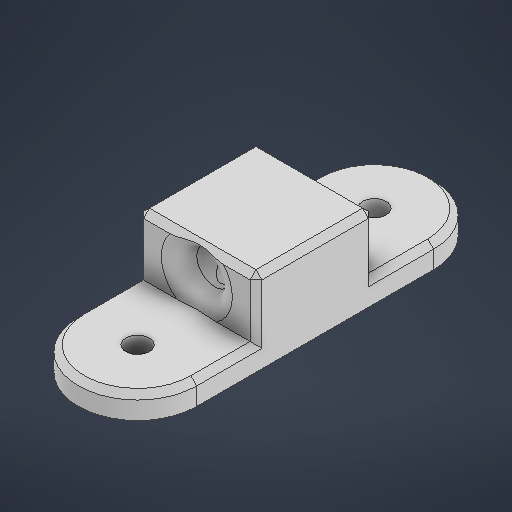
# Autodesk Inventor part: 1_1_10_1_directeur_de_cable
Saved by Autodesk Inventor 2026 (Build 300175000, 175)
## iProperties
Created: 2025-05-30
Part Number: 1_1_10_1_directeur_de_cable
Material: Generic
Document SubType Name: Modeling
Designer: remg9
Density: 1 g/cm^3
Appearance: Default
Author: remg9
Autodesk Inventor part; units mm, degrees
ref_plane "YZ Plane" through (0, 0, 0) normal (1, 0, 0) x (0, 1, 0)
ref_plane "XZ Plane" through (0, 0, 0) normal (0, 1, 0) x (-1, 0, 0)
ref_plane "XY Plane" through (0, 0, 0) normal (0, 0, 1) x (1, 0, 0)
sketch "Sketch1" plane through (0, 0, 0) normal (0, 1, 0) x (-1, 0, 0)
  line L0 (-10, 30) -> (10, 30)
  line L1 (10, 30) -> (10, -30)
  line L2 (10, -30) -> (-10, -30)
  line L3 (-10, -30) -> (-10, 30)
  line L4 (-10, 30) -> (10, -30) construction
  line L5 (10, 30) -> (-10, -30) construction
  point P0 (0, 0)
  dimension "d0" = 60
  dimension "d1" = 20
  constraints: 12 end point, 2 midpoint, 2 parallel, 1 horizontal, 1 perpendicular
  measures "d0" distance of L2.end L0.start
  measures "d1" distance of L1.end L2.end
extrude "Extrusion1" add sketch "Sketch1" along normal blind 4
sketch "Sketch2" plane through (0, 4, 0) normal (0, 1, 0) x (1, 0, 0)
  line L0 (-10, -10) -> (10, -10)
  line L1 (10, -10) -> (10, 10)
  line L2 (10, 10) -> (-10, 10)
  line L3 (-10, 10) -> (-10, -10)
  line L4 (-10, 30) -> (-10, -30) projected
  line L5 (10, -30) -> (10, 30) projected
  line L6 (-10, -30) -> (10, -30) projected
  line L7 (10, 30) -> (-10, 30) projected
  point P0 (0, 0)
  dimension "d4" = 20
  dimension "d5" = 20
  constraints: 8 end point, 2 collinear, 2 parallel, 1 horizontal, 1 perpendicular
  measures "d4" distance between parallel lines of L6 L0
  measures "d5" distance between parallel lines of L7 L2
extrude "Extrusion2" add sketch "Sketch2" along normal blind 10 contours L3 L2 L1 L0
sketch "Sketch4" plane through (-10, 4, 10) normal (0, 0, 1) x (1, 0, 0)
  circle A0 centre (10, 5) radius 3
  line L0 (20, 0) -> (20, 10) projected
  line L1 (0, 0) -> (20, 0) projected
  dimension "d43" = 6
  dimension "d44" = 10
  dimension "d45" = 5
  constraints: 1 centre point
  measures "d43" diameter of A0
  measures "d44" distance from line of L0 A0.centre
  measures "d45" distance from line of L1 A0.centre
extrude "Extrusion3" cut sketch "Sketch4" against normal through all
sketch "Sketch5" plane through (0, 0, 0) normal (0, -1, 0) x (1, 0, 0)
  circle A0 centre (0, 0) radius 3
  dimension "d18" = 6
  constraints: 1 centre point, 1 coincident
  measures "d18" diameter of A0
extrude "Extrusion4" cut sketch "Sketch5" against normal blind 9
fillet "Fillet2" radius 10 4 edges at (10, 2, -30) (-10, 2, -30) (-10, 2, 30) (10, 2, 30)
sketch "Sketch6" plane through (0, 4, 0) normal (0, 1, 0) x (1, 0, 0)
  line L0 (-10, -9) -> (-10, -30) projected
  line L1 (-10, -30) -> (10, -30) projected
  line L2 (-10, 30) -> (-10, 9) projected
  line L3 (10, 30) -> (-10, 30) projected
  point P0 (0, 0)
  point P1 (0, -20)
  point P2 (0, 20)
  dimension "d28" = 10
  dimension "d29" = 10
  dimension "d30" = 10
  dimension "d31" = 10
  measures "d28" distance from line of L0 point (0, -20)
  measures "d29" distance from line of L1 point (0, -20)
  measures "d30" distance from line of L2 point (0, 20)
  measures "d31" distance from line of L3 point (0, 20)
hole "Hole1" at (0, 4, 20) at (0, 4, -20) direction (0, -1, 0) diameter 4 end through all
chamfer "Chamfer3" distance 1 angle 45 18 edges at (0, 4, 30) (-7.0711, 4, 27.0711) (7.0711, 4, 27.0711) (-10, 4, 15.0001) (10, 4, 15) (10, 9, 10) (0, 14, 10) (10, 14, 0) (-10, 9, 10) (-10, 14, 0) (-10, 4, -15) (7.0711, 4, -27.0711) (-7.0711, 4, -27.0711) (0, 4, -30) (10, 4, -15.0001) (-10, 9, -10) (10, 9, -10) (0, 14, -10)
fillet "Fillet3" radius 3 5 edges at (-3, 9, -10) (0, 6, -3) (-2.1213, 6.8787, 2.1213) (2.1213, 6.8787, 2.1213) (-3, 9, 10)
body "Solid1"
